Fork native (Autodesk Fusion 360 design; units mm, degrees)
part number: 2026-10-13-21-25-05-703
Autodesk Fusion 360 part; units mm, degrees
ref_plane "WorkPlane1" through (0, 2.3, 0) normal (0, 1, 0) x (0, 0, 1)
sketch "Plate" plane through (0, 2.3, 0) normal (0, 1, 0) x (1, 0, 0)
  line L0 (3.3594, -7.6547) -> (3.3594, -14.5)
  arc A0 (-3.3594, -14.5) -> (3.3594, -14.5) centre (0, -14.5) ccw
  line L1 (-3.3594, -14.5) -> (-3.3594, -7.6547)
  arc A1 (-8.3594, 0) -> (-3.3594, -7.6547) centre (0, 0) ccw
  line L2 (-8.3594, 0) -> (-8.3594, 4.9)
  line L3 (-8.3594, 4.9) -> (-3.3594, 4.9)
  line L4 (-3.3594, 4.9) -> (-3.3594, 0)
  arc A2 (-3.3594, 0) -> (3.3594, 0) centre (0, 0) ccw
  line L5 (3.3594, 0) -> (3.3594, 4.9)
  line L6 (3.3594, 4.9) -> (8.3594, 4.9)
  line L7 (8.3594, 4.9) -> (8.3594, 0)
  arc A3 (3.3594, -7.6547) -> (8.3594, 0) centre (0, 0) ccw
  dimension "d23" = 3.3594
  dimension "d24" = 8.3594
  dimension "d25" = 14.5
  dimension "d26" = 4.9
  dimension "d27" = 4.9
  constraint vertical L0
  constraint vertical L1
  constraint vertical L2
  constraint horizontal L3
  constraint vertical L4
  constraint vertical L5
  constraint horizontal L6
  constraint vertical L7
  constraint tangent L0 A0
  constraint tangent A0 L1
  constraint tangent A1 L2
  constraint tangent L4 A2
  constraint tangent A2 L5
  constraint tangent L7 A3
  constraint coincident A1.centre A2.centre
  constraint equal A0 A2
  constraint equal A1 A3
  constraint vertical A1.centre A0.centre
  measures "d23" radius of A0
  measures "d24" radius of A1
  measures "d25" vertical distance of A1.centre A0.centre
  measures "d26" vertical distance of A1.centre L2.end
  measures "d27" vertical distance of A1.centre L5.end
extrude "Plate (1)" add sketch "Plate" along normal mid plane 2
ref_plane "WorkPlane2" through (0, 4.05, 0) normal (0, 1, 0) x (0, 0, 1)
sketch "Boss" plane through (0, 4.05, 0) normal (0, 1, 0) x (1, 0, 0)
  circle A0 centre (0, -14.5) radius 3.3594
  dimension "d28" = 6.7188
  dimension "d29" = 14.5
  constraint vertical origin A0.centre
  measures "d28" diameter of A0
  measures "d29" vertical distance of origin A0.centre
extrude "Boss (1)" add sketch "Boss" along normal mid plane 1.5
ref_plane "WorkPlane3" through (0, 2.3, 0) normal (0, 1, 0) x (0, 0, 1)
sketch "Arm hole +X" plane through (0, 2.3, 0) normal (0, 1, 0) x (1, 0, 0)
  circle A0 centre (5.8594, 1.95) radius 1.75
  dimension "d30" = 3.5
  dimension "d31" = 5.8594
  dimension "d32" = 1.95
  measures "d30" diameter of A0
  measures "d31" horizontal distance of origin A0.centre
  measures "d32" vertical distance of origin A0.centre
extrude "Arm hole +X (1)" cut sketch "Arm hole +X" along normal mid plane 2
ref_plane "WorkPlane4" through (0, 2.3, 0) normal (0, 1, 0) x (0, 0, 1)
sketch "Arm hole -X" plane through (0, 2.3, 0) normal (0, 1, 0) x (1, 0, 0)
  circle A0 centre (-5.8594, 1.95) radius 1.75
  dimension "d33" = 3.5
  dimension "d34" = 5.8594
  dimension "d35" = 1.95
  measures "d33" diameter of A0
  measures "d34" horizontal distance of origin A0.centre
  measures "d35" vertical distance of origin A0.centre
extrude "Arm hole -X (1)" cut sketch "Arm hole -X" along normal mid plane 2
ref_plane "WorkPlane5" through (0, 3.05, 0) normal (0, 1, 0) x (0, 0, 1)
sketch "Top hole" plane through (0, 3.05, 0) normal (0, 1, 0) x (1, 0, 0)
  circle A0 centre (0, -14.5) radius 1.5
  dimension "d36" = 3
  dimension "d37" = 14.5
  constraint vertical origin A0.centre
  measures "d36" diameter of A0
  measures "d37" vertical distance of origin A0.centre
extrude "Top hole (1)" cut sketch "Top hole" along normal mid plane 3.5
chamfer "Outer chamfer" distance 0.5 distance2 1.5 4 edges at (6.9986, 3.3, 4.5715) (8.3594, 3.3, -2.45) (-8.3594, 3.3, -2.45) (-6.9986, 3.3, 4.5715) measured on face at (0.0837, 3.3, 6.2198) measured on face at (0.0837, 3.3, 6.2198) measured on face at (0.0837, 3.3, 6.2198) measured on face at (0.0837, 3.3, 6.2198) tangent chain off
named bodies: "Fork native"
